bottom (Autodesk Fusion 360 design; units mm, degrees)
Autodesk Fusion 360 part; units mm, degrees
sketch "스케치1" plane through (0, 0, 3) normal (0, 0, 1) x (-1, 0, 0)
  line L0 (-33, -7) -> (-83, -7)
  line L1 (-83, -7) -> (-83, -37)
  line L2 (-83, -37) -> (-33, -37)
  line L3 (-33, -37) -> (-33, -7)
  circle A0 centre (-38.35, -22) radius 1.5
  circle A1 centre (-77.65, -22) radius 1.5
  dimension "d1" = 3
  dimension "d2" = 3
  dimension "d3" = 15
  dimension "d4" = 15
  dimension "d5" = 39.3
  dimension "d6" = 5.35
  measures "d1" diameter of A0
  measures "d2" diameter of A1
  measures "d3" distance of L2 A0.centre
  measures "d4" distance of L2 A1.centre
  measures "d5" distance of A0.centre A1.centre
  measures "d6" distance of L3 A0.centre
sketch "스케치2" plane through (0, 0, 0) normal (0, 0, 1) x (1, 0, 0)
  line L0 (33, 37) -> (83, 37)
  line L1 (83, 37) -> (83, 7)
  line L2 (83, 7) -> (33, 7)
  line L3 (33, 7) -> (33, 37)
  dimension "d7" = 50
  dimension "d8" = 30
  constraint horizontal L0
  constraint vertical L1
  constraint horizontal L2
  constraint vertical L3
  measures "d7" distance of L0.start L0.end
  measures "d8" distance of L0.start L2.end
extrude "돌출1" add sketch "스케치2" along normal blind 3
extrude "돌출2" add sketch "스케치1" along normal blind 16 contours A0 | A1
extrude "돌출3" cut 2 faces at (77.7613, 21.5125, 19) (37.9835, 21.6599, 19) along direction (0, 0, -1) blind 1
extrude "돌출4" add 2 faces at (77.7613, 21.5125, 18) (37.9835, 21.6599, 18) along direction (0, 0, 1) blind 1
sketch "sketch 746" plane through (-3.7512, 0.7214, 3) normal (0, 0, 1) x (-1, 0, 0)
  line L0 (-64.2512, -33.2786) -> (-64.2512, -36.2786)
  line L1 (-64.2512, -36.2786) -> (-59.2512, -36.2786)
  line L2 (-64.2512, -36.2786) -> (-59.2512, -36.2786)
  line L3 (-59.2512, -36.2786) -> (-59.2512, -33.2786)
  line L4 (-59.2512, -33.2786) -> (-64.2512, -33.2786)
  line L5 (-59.2512, -9.2786) -> (-64.2512, -9.2786)
  line L6 (-59.2512, -6.2786) -> (-59.2512, -9.2786)
  line L7 (-64.2512, -6.2786) -> (-59.2512, -6.2786)
  line L8 (-64.2512, -6.2786) -> (-59.2512, -6.2786)
  line L9 (-64.2512, -9.2786) -> (-64.2512, -6.2786)
extrude "돌출5" add sketch "sketch 746" along normal blind 21
extrude "돌출6" add 1 faces at (57.1667, 9, 24) along direction (0, 0, 1) blind 3
